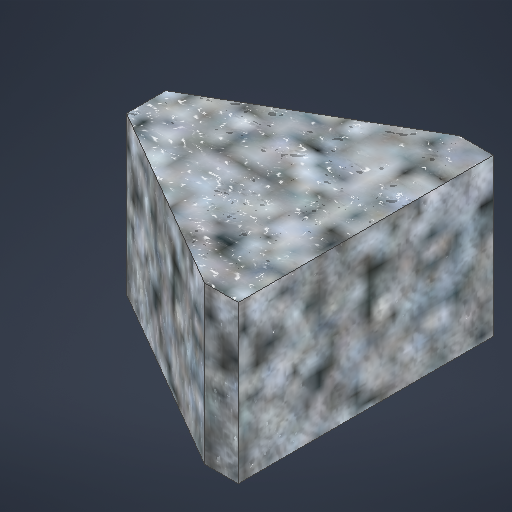
# Autodesk Inventor part: Ta bang inox
Saved by Autodesk Inventor 2027 (Build 310192060, 192F)
## iProperties
Created: 2026-07-08
Part Number: Ta bang inox
Material: Generic
Document SubType Name: Modeling
Designer: Laptop
Density: 1 g/cm^3
Appearance: Industrial Floor
Author: Laptop
Autodesk Inventor part; units mm, degrees
ref_plane "YZ Plane" through (0, 0, 0) normal (1, 0, 0) x (0, 1, 0)
ref_plane "XZ Plane" through (0, 0, 0) normal (0, 1, 0) x (-1, 0, 0)
ref_plane "XY Plane" through (0, 0, 0) normal (0, 0, 1) x (1, 0, 0)
sketch "Sketch1" plane through (0, 0, 0) normal (0, 1, 0) x (-1, 0, 0)
  line L0 (0, 0) -> (8.6, 0)
  line L1 (8.6, -65) -> (0, -65)
  line L2 (0, -65) -> (0, 0)
  line L3 (56, -32.5) -> (56, -27.5)
  line L4 (56, -32.5) -> (56, -37.5)
  line L5 (56, -37.5) -> (8.6, -65)
  line L6 (56, -27.5) -> (8.6, 0)
  dimension "d0" = 8.6
  dimension "d1" = 65
  dimension "d3" = 5
  dimension "d4" = 5
  constraints: 14 end point, 1 horizontal, 1 parallel, 1 vertical
  measures "d0" distance of L1.start L1.end
  measures "d1" distance of L0.end L1.start
  measures "d3" distance of L3.start L3.end
  measures "d4" distance of L3.start L4.end
extrude "Extrusion1" add sketch "Sketch1" along normal blind 40
body "Solid1"
